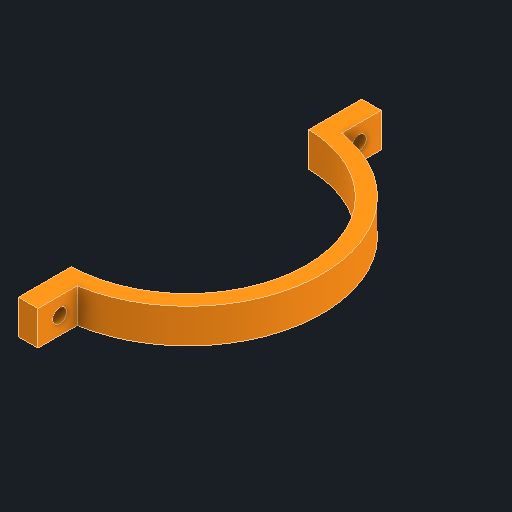
# Autodesk Inventor part: dec_clamp_cap
Saved by Autodesk Inventor 2027.1 (Build 311270010, 270A)
## iProperties
Created: 2026-11-04
Part Number: dec_clamp_cap
Material: Generic
Description: Dec clamp cap: other half of the Dec housing clamp ring, 2x M4x16 into inserts in the bracket
Document SubType Name: Modeling
Designer: Claude (from photos)
Density: 1 g/cm^3
Appearance: Orange
Author: alexg
Autodesk Inventor part; units mm, degrees
ref_plane "Work Plane1" through (0, 47, 0) normal (0, 1, 0) x (-1, 0, 0)
sketch "Clamp ring sketch" plane through (0, 47, 0) normal (0, 1, 0) x (-1, 0, 0)
  circle A0 centre (-187, 0) radius 43
  circle A1 centre (-187, 0) radius 38
  constraints: 2 centre point
extrude "Clamp ring" add sketch "Clamp ring sketch" along normal blind 11
ref_plane "Work Plane2" through (0, 47, 0) normal (0, 1, 0) x (-1, 0, 0)
sketch "Keep the far half sketch" plane through (0, 47, 0) normal (0, 1, 0) x (-1, 0, 0)
  line L0 (-127, -60) -> (-187.75, -60)
  line L1 (-187.75, -60) -> (-187.75, 60)
  line L2 (-187.75, 60) -> (-127, 60)
  line L3 (-127, 60) -> (-127, -60)
  constraints: 8 end point, 2 parallel, 1 horizontal, 1 perpendicular
extrude "Keep the far half" cut sketch "Keep the far half sketch" along normal blind 11
ref_plane "Work Plane3" through (0, 47, 0) normal (0, 1, 0) x (-1, 0, 0)
sketch "Clamp ears sketch" plane through (0, 47, 0) normal (0, 1, 0) x (-1, 0, 0)
  line L0 (-187.75, 41) -> (-194, 41)
  line L1 (-194, 41) -> (-194, 55)
  line L2 (-194, 55) -> (-187.75, 55)
  line L3 (-187.75, 55) -> (-187.75, 41)
  line L4 (-187.75, -55) -> (-194, -55)
  line L5 (-194, -55) -> (-194, -41)
  line L6 (-194, -41) -> (-187.75, -41)
  line L7 (-187.75, -41) -> (-187.75, -55)
  constraints: 16 end point, 4 parallel, 2 horizontal, 2 perpendicular
extrude "Clamp ears" add sketch "Clamp ears sketch" along normal blind 11
ref_plane "Work Plane4" through (187.75, 0, 0) normal (1, 0, 0) x (0, 1, 0)
sketch "M4 clearance holes sketch" plane through (187.75, 0, 0) normal (1, 0, 0) x (0, 1, 0)
  circle A0 centre (52.5, 48) radius 2.25
  circle A1 centre (52.5, -48) radius 2.25
  constraints: 2 centre point
extrude "M4 clearance holes" cut sketch "M4 clearance holes sketch" along normal blind 10
body "Solid1"
